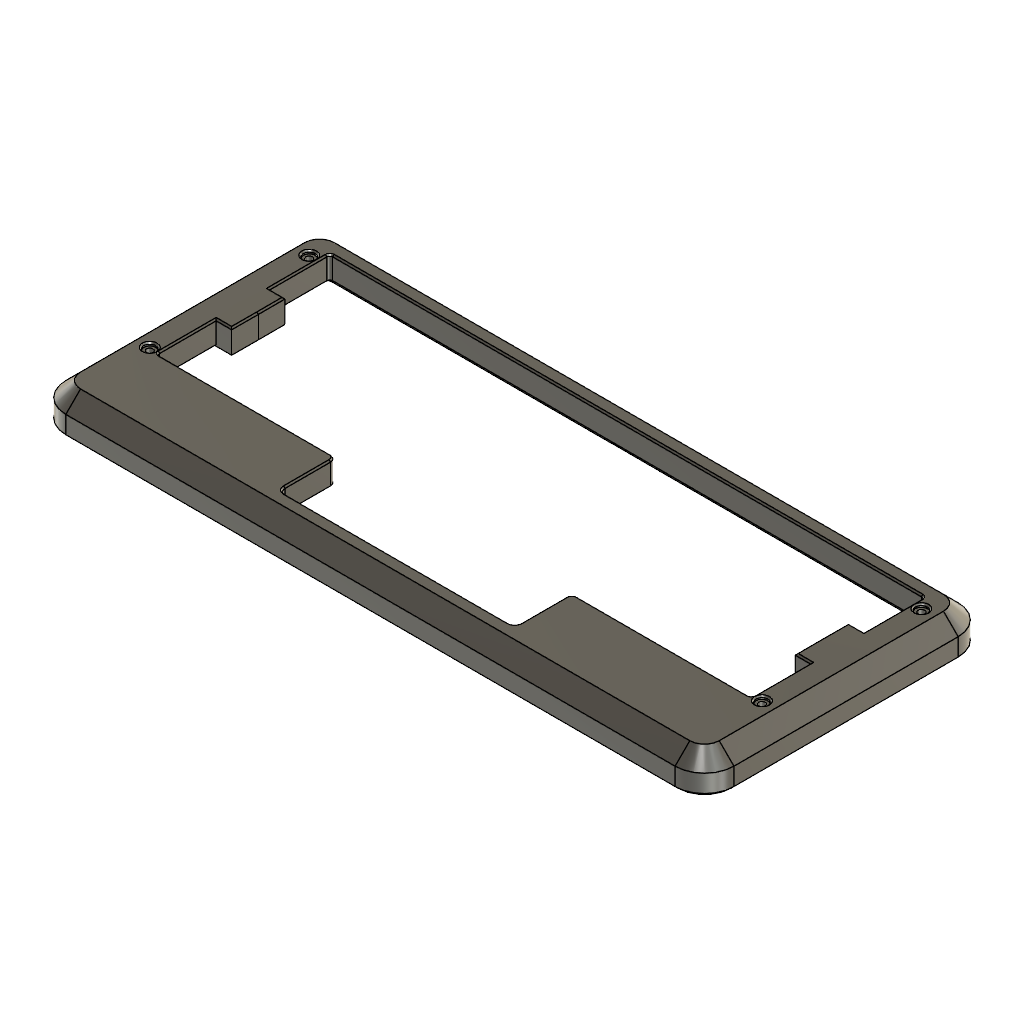
Hullstone Cover Top (Autodesk Fusion 360 design; units mm, degrees)
Autodesk Fusion 360 part; units mm, degrees
sketch "Sketch1" plane through (0, 0, 0) normal (0, 0, 1) x (1, 0, 0)
  circle A0 centre (-4, -3) radius 1.1
  line L0 (142.0125, -57.775) -> (200.025, -57.775)
  line L1 (-3.9994, -3.7) -> (-4, -3.7)
  arc A1 (204.025, -3.7) -> (204.0253, -3.7) centre (204.025, -3) ccw
  circle A2 centre (204.025, -3) radius 1.1
  arc A3 (-4.0003, -3.7) -> (-4, -3.7) centre (-4, -3) ccw
  circle A4 centre (204.025, -57.175) radius 1.1
  circle A5 centre (-4, -57.175) radius 1.1
  line L2 (204.0245, -3.7) -> (204.025, -3.7)
  line L3 (200.025, 1) -> (0, 1)
  line L4 (-10.5, -2.5) -> (-10.5, -75.2)
  arc A6 (-10.5, -75.2) -> (-4, -81.7) centre (-4, -75.2) ccw
  line L5 (100.0125, -81.7) -> (-4, -81.7)
  line L6 (100.0125, -81.7) -> (204.025, -81.7)
  arc A7 (204.025, -81.7) -> (210.525, -75.2) centre (204.025, -75.2) ccw
  line L7 (210.525, -2.5) -> (210.525, -75.2)
  arc A8 (210.525, -2.5) -> (204.025, 4) centre (204.025, -2.5) ccw
  line L8 (100.0125, 4) -> (204.025, 4)
  line L9 (100.0125, 4) -> (-4, 4)
  arc A9 (-4, 4) -> (-10.5, -2.5) centre (-4, -2.5) ccw
  line L10 (100.0125, 10) -> (-3.5, 10)
  line L11 (100.0125, 10) -> (203.525, 10)
  line L12 (210.525, -38.85) -> (213.525, -38.85)
  line L13 (213.525, -38.85) -> (213.525, 0)
  line L14 (213.525, -38.85) -> (213.525, -76.2)
  line L15 (100.0125, -86.2) -> (203.525, -86.2)
  line L16 (-10.5, -38.85) -> (-13.5, -38.85)
  line L17 (-13.5, -38.85) -> (-13.5, -76.2)
  line L18 (-13.5, -38.85) -> (-13.5, 0)
  line L19 (100.0125, -86.2) -> (-3.5, -86.2)
  arc A10 (-13.5, -76.2) -> (-3.5, -86.2) centre (-3.5, -76.2) ccw
  arc A11 (203.525, -86.2) -> (213.525, -76.2) centre (203.525, -76.2) ccw
  arc A12 (213.525, 0) -> (203.525, 10) centre (203.525, 0) ccw
  arc A13 (-3.5, 10) -> (-13.5, 0) centre (-3.5, 0) ccw
  arc A14 (-1, -56.775) -> (0, -57.775) centre (0, -56.775) ccw
  arc A15 (0, 1) -> (-1, 0) centre (0, 0) ccw
  arc A16 (201.025, 0) -> (200.025, 1) centre (200.025, 0) ccw
  arc A17 (200.025, -57.775) -> (201.025, -56.775) centre (200.025, -56.775) ccw
  line L20 (195.7625, -19.525) -> (201.025, -19.525)
  line L21 (195.7375, -28.575) -> (195.7625, -19.525)
  line L22 (195.7625, -37.625) -> (201.025, -37.625)
  line L23 (195.7375, -28.575) -> (195.7625, -37.625)
  line L24 (4.2625, -19.525) -> (-1, -19.525)
  line L25 (4.2625, -37.625) -> (-1, -37.625)
  line L26 (4.2875, -28.575) -> (4.2625, -37.625)
  line L27 (4.2875, -28.575) -> (4.2625, -19.525)
  line L28 (-1, 0) -> (-1, -19.525)
  line L29 (-1, -37.625) -> (-1, -56.775)
  line L30 (201.025, -56.775) -> (201.025, -37.625)
  line L31 (201.025, -19.525) -> (201.025, 0)
  line L32 (100.0125, -77.2) -> (60.0125, -77.2)
  line L33 (100.0125, -77.2) -> (62.0125, -77.2)
  line L34 (60.0125, -75.2) -> (60.0125, -59.775)
  line L35 (58.0125, -57.775) -> (0, -57.775)
  line L36 (100.0125, -77.2) -> (138.0125, -77.2)
  line L37 (140.0125, -75.2) -> (140.0125, -59.775)
  arc A18 (142.0125, -57.775) -> (140.0125, -59.775) centre (142.0125, -59.775) ccw
  arc A19 (138.0125, -77.2) -> (140.0125, -75.2) centre (138.0125, -75.2) ccw
  arc A20 (60.0125, -75.2) -> (62.0125, -77.2) centre (62.0125, -75.2) ccw
  arc A21 (60.0125, -59.775) -> (58.0125, -57.775) centre (58.0125, -59.775) ccw
  point P0 (201.025, -61.175)
  point P1 (140.0125, -77.2)
  dimension "d2" = 3
  dimension "d3" = 2.2
  dimension "d4" = 2.2
  dimension "d5" = 2.2
  dimension "d6" = 2.2
  dimension "d9" = 3
  dimension "d10" = 4.5
  dimension "d11" = 3
  dimension "d12" = 10
  dimension "d34" = 1
  dimension "d51" = 40
  dimension "d52" = 40
  dimension "d53" = 2
  constraint concentric A0 A3
  constraint concentric A1 A2
  constraint tangent L4 A6
  constraint tangent L4 A9
  constraint tangent A6 L5
  constraint tangent L6 A7
  constraint tangent L7 A8
  constraint tangent A7 L7
  constraint tangent A8 L8
  constraint tangent L9 A9
  constraint midpoint L7 L12.start
  constraint perpendicular L7 L12
  constraint perpendicular L11 L13
  constraint perpendicular L12 L14
  constraint perpendicular L14 L15
  constraint midpoint L4 L16.start
  constraint perpendicular L4 L16
  constraint perpendicular L16 L17
  constraint perpendicular L10 L18
  constraint perpendicular L17 L19
  constraint tangent L19 A10
  constraint tangent L17 A10
  constraint tangent L15 A11
  constraint tangent L14 A11
  constraint equal A10 A11
  constraint tangent L13 A12
  constraint tangent L11 A12
  constraint equal A10 A12
  constraint tangent L10 A13
  constraint tangent L18 A13
  constraint equal A10 A13
  constraint tangent A14 L28
  constraint tangent A15 L28
  constraint tangent L3 A15
  constraint equal A14 A15
  constraint tangent L3 A16
  constraint tangent A16 L30
  constraint equal A14 A16
  constraint tangent A17 L30
  constraint tangent L0 A17
  constraint equal A14 A17
  constraint coincident L20.end L30
  constraint perpendicular L20 L30
  constraint perpendicular L22 L30
  constraint perpendicular L24 L28
  constraint coincident L25.end L28
  constraint perpendicular L25 L28
  constraint collinear L28 L29
  constraint collinear L30 L31
  constraint perpendicular L0 L34
  constraint tangent A14 L35
  constraint perpendicular L0 L37
  constraint tangent L0 A18
  constraint tangent L37 A18
  constraint coincident P1 L37
  constraint coincident P1 L36
  constraint tangent L37 A19
  constraint tangent L36 A19
  constraint equal A18 A19
  constraint coincident L32.end L34
  constraint tangent L33 A20
  constraint tangent L34 A20
  constraint equal A18 A20
  constraint tangent L34 A21
  constraint tangent L35 A21
  constraint equal A18 A21
  measures "d2" distance of A5.centre L28
  measures "d3" diameter of A5
  measures "d4" diameter of A0
  measures "d5" diameter of A2
  measures "d6" diameter of A4
  measures "d9" distance of L12.start L12.end
  measures "d10" distance of L5.start L15.start
  measures "d11" distance of L16.start L16.end
  measures "d12" radius of A10
  measures "d34" radius of A14
  measures "d51" distance of L32.start L32.end
  measures "d52" distance of L32.start P1
  measures "d53" radius of A18
extrude "Extrude1" add sketch "Sketch1" along normal blind 8 contours L4 A6 L5 L6 A7 L7 A8 L8 L9 A9 | L4 L7 A8 L8 L9 A9 L10 L11 L12 L13 L16 L18 A12 A13 | L4 A6 L5 L6 A7 L7 L12 L14 L15 L16 L17 L19 A10 A11
extrude "Extrude2" add sketch "Sketch1" against normal blind 4 contours L4 L7 A8 L8 L9 A9 L10 L11 L12 L13 L16 L18 A12 A13 | L4 A6 L5 L6 A7 L7 L12 L14 L15 L16 L17 L19 A10 A11
sketch "Sketch2" plane through (0, 10, 0) normal (0, 1, 0) x (-1, 0, 0)
  line L0 (3.5, -4) -> (3.5, 8)
  line L1 (3.5, 8) -> (-203.525, 8)
  line L2 (-203.525, 8) -> (-203.525, -4)
  line L3 (-203.525, -4) -> (3.5, -4)
  line L4 (-109, -4.0094) -> (-109, -4)
  line L5 (-91.0001, -3.9531) -> (-91, -4)
  line L6 (-108.0031, -3.0062) -> (-92.0033, -2.9563)
  arc A0 (-108.0031, -3.0062) -> (-109, -4.0094) centre (-108, -4.0062) ccw
  arc A1 (-91.0001, -3.9531) -> (-92.0033, -2.9563) centre (-92.0001, -3.9563) ccw
  point P0 (-100.0125, 0)
  point P1 (-91.0125, 0)
  point P2 (-109.0125, 0)
  dimension "d48" = 1
  constraint coincident L3 L4.end
  constraint coincident L3 L5.end
  constraint coincident P2 L4
  constraint coincident P1 L5
  constraint perpendicular L4 L6
  constraint perpendicular L5 L6
  constraint tangent L4 A0
  constraint tangent L6 A0
  constraint tangent L6 A1
  constraint tangent L5 A1
  constraint equal A0 A1
  measures "d48" radius of A0
extrude "Extrude3" cut sketch "Sketch2" against normal blind 6 contours L3 L5 L6 A0 A1
sketch "Sketch3" plane through (0, 0, 8) normal (0, 0, 1) x (-1, 0, 0)
  line L0 (-200.025, 57.775) -> (-142.0125, 57.775)
  line L1 (1, 56.775) -> (1, 37.625)
  line L2 (0, -1) -> (-200.025, -1)
  line L3 (-201.025, 37.625) -> (-201.025, 56.775)
  circle A0 centre (-204.025, 57.175) radius 1.1
  circle A1 centre (-204.025, 3) radius 1.1
  circle A2 centre (4, 57.175) radius 1.1
  circle A3 centre (4, 3) radius 1.1
  arc A4 (3.5, -10) -> (13.5, 0) centre (3.5, 0) ccw
  line L4 (13.5, 0) -> (13.5, 76.2)
  arc A5 (13.5, 76.2) -> (3.5, 86.2) centre (3.5, 76.2) ccw
  line L5 (3.5, 86.2) -> (-203.525, 86.2)
  arc A6 (-203.525, 86.2) -> (-213.525, 76.2) centre (-203.525, 76.2) ccw
  line L6 (-213.525, 76.2) -> (-213.525, 0)
  arc A7 (-213.525, 0) -> (-203.525, -10) centre (-203.525, 0) ccw
  circle A8 centre (4, 3) radius 2
  circle A9 centre (4, 57.175) radius 2
  circle A10 centre (-204.025, 57.175) radius 2
  circle A11 centre (-204.025, 3) radius 2
  arc A12 (1, 56.775) -> (0, 57.775) centre (0, 56.775) ccw
  arc A13 (0, -1) -> (1, 0) centre (0, 0) ccw
  arc A14 (-201.025, 0) -> (-200.025, -1) centre (-200.025, 0) ccw
  arc A15 (-200.025, 57.775) -> (-201.025, 56.775) centre (-200.025, 56.775) ccw
  line L7 (-195.7625, 19.525) -> (-195.7375, 28.575)
  line L8 (-195.7375, 28.575) -> (-195.7625, 37.625)
  line L9 (-195.7625, 37.625) -> (-201.025, 37.625)
  line L10 (1, 37.625) -> (-4.2625, 37.625)
  line L11 (-4.2625, 37.625) -> (-4.2875, 28.575)
  line L12 (-4.2875, 28.575) -> (-4.2625, 19.525)
  line L13 (-4.2625, 19.525) -> (1, 19.525)
  line L14 (1, 19.525) -> (1, 0)
  line L15 (-201.025, 0) -> (-201.025, 19.525)
  line L16 (-201.025, 19.525) -> (-195.7625, 19.525)
  line L17 (-203.525, -10) -> (3.5, -10)
  arc A16 (-60.0125, 75.2) -> (-62.0125, 77.2) centre (-62.0125, 75.2) ccw
  line L18 (-60.0125, 75.2) -> (-60.0125, 59.775)
  arc A17 (-60.0125, 59.775) -> (-58.0125, 57.775) centre (-58.0125, 59.775) ccw
  line L19 (-58.0125, 57.775) -> (0, 57.775)
  arc A18 (-142.0125, 57.775) -> (-140.0125, 59.775) centre (-142.0125, 59.775) ccw
  line L20 (-140.0125, 59.775) -> (-140.0125, 75.2)
  arc A19 (-138.0125, 77.2) -> (-140.0125, 75.2) centre (-138.0125, 75.2) ccw
  line L21 (-138.0125, 77.2) -> (-62.0125, 77.2)
  dimension "d24" = 4
  dimension "d25" = 4
  dimension "d26" = 4
  dimension "d27" = 4
  constraint concentric A3 A8
  constraint concentric A2 A9
  constraint concentric A0 A10
  constraint concentric A1 A11
  measures "d24" diameter of A8
  measures "d25" diameter of A9
  measures "d26" diameter of A10
  measures "d27" diameter of A11
extrude "Extrude4" cut sketch "Sketch3" against normal blind 1 contours A8 | A9 | A10 | A11
chamfer "Chamfer1" distance 0.5 angle 45 4 edges at (-2.1353, -3.7232, 8) (-2.1353, -57.8982, 8) (205.8897, -3.7232, 8) (205.8897, -57.8982, 8) tangent chain off
chamfer "Chamfer2" distance 5 angle 45 8 edges at (100.0125, 10, 8) (-10.5711, 7.0711, 8) (-13.5, -38.1, 8) (-10.5711, -83.2711, 8) (100.0125, -86.2, 8) (210.5961, -83.2711, 8) (213.525, -38.1, 8) (210.5961, 7.0711, 8) tangent chain off
chamfer "Chamfer4" distance 0.5 angle 45 18 edges at (100.0125, 1, 0) (-0.7071, 0.7071, 0) (-1, -9.7625, 0) (201.025, -9.7625, 0) (200.7321, 0.7071, 0) (201.025, -47.2, 0) (200.7321, -57.4821, 0) (171.0188, -57.775, 0) (140.5983, -58.3608, 0) (140.0125, -67.4875, 0) (139.4267, -76.6142, 0) (100.0125, -77.2, 0) (60.5983, -76.6142, 0) (60.0125, -67.4875, 0) (59.4267, -58.3608, 0) (29.0062, -57.775, 0) (-0.7071, -57.4821, 0) (-1, -47.2, 0) tangent chain off
chamfer "Chamfer5" distance 1 angle 45 9 edges at (100.0125, -81.7, -4) (208.6212, -79.7962, -4) (210.525, -38.85, -4) (208.6212, 2.0962, -4) (156.5125, 4, -4) (43.5, 4, -4) (-8.5962, 2.0962, -4) (-10.5, -38.85, -4) (-8.5962, -79.7962, -4) tangent chain off
chamfer "Chamfer6" distance 1 angle 45 10 edges at (156.2625, 10, -4) (43.75, 10, -4) (210.5961, 7.0711, -4) (213.525, -38.1, -4) (210.5961, -83.2711, -4) (100.0125, -86.2, -4) (-10.5711, -83.2711, -4) (-13.5, -38.1, -4) (-10.5711, 7.0711, -4) (43.75, 10, -4) tangent chain off
chamfer "Chamfer7" distance 0.5 angle 45 26 edges at (171.0188, -57.775, 8) (140.5983, -58.3608, 8) (140.0125, -67.4875, 8) (139.4267, -76.6142, 8) (100.0125, -77.2, 8) (60.5983, -76.6142, 8) (60.0125, -67.4875, 8) (59.4267, -58.3608, 8) (29.0062, -57.775, 8) (-0.7071, -57.4821, 8) (-1, -47.2, 8) (201.025, -47.2, 8) (200.7321, -57.4821, 8) (1.6312, -37.625, 8) (4.275, -33.1, 8) (4.275, -24.05, 8) (1.6312, -19.525, 8) (-1, -9.7625, 8) (-0.7071, 0.7071, 8) (100.0125, 1, 8) (200.7321, 0.7071, 8) (201.025, -9.7625, 8) (198.3938, -19.525, 8) (195.75, -24.05, 8) (195.75, -33.1, 8) (198.3938, -37.625, 8) tangent chain off
